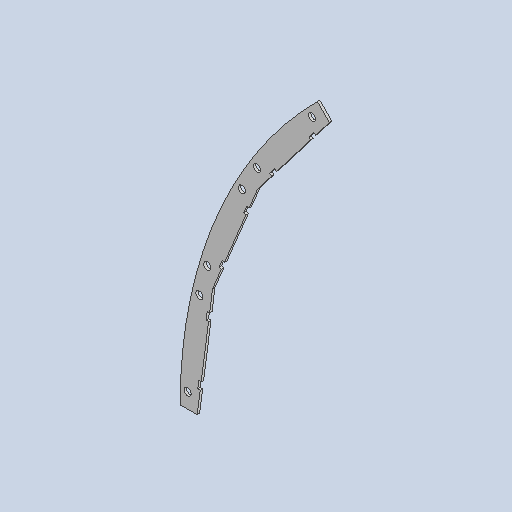
# Autodesk Inventor part: DMF-1209 Gear Rim 02
Saved by Autodesk Inventor 2026.2 (Build 302298000, 298)
## iProperties
Created: 2024-04-30
Part Number: DMF-1209 Gear Rim 02
Material: Stainless Steel
Document SubType Name: Sheet Metal
Designer: admin
Stock Number: DMF-1209
Mass: 249.053 g
Surface Area: 241.922 cm^2
Volume: 31.1317 cm^3
Density: 8 g/cm^3
Flat Pattern Width: 6.39586 cm
Flat Pattern Length: 44.6209 cm
Flat Pattern Area: 285.389 cm^2
Sheet Metal Rule: Default
Sheet Metal Width: 63,959 mm
Sheet Metal Length: 446,209 mm
Sheet Metal Area: 28538,909 mm^2
Appearance: Default
Rim1209_Chord_Length: 146,661 mm
Author: pokla
Autodesk Inventor part; units mm, degrees
ref_plane "YZ Plane" through (0, 0, 0) normal (1, 0, 0) x (0, 1, 0)
ref_plane "XZ Plane" through (0, 0, 0) normal (0, 1, 0) x (-1, 0, 0)
ref_plane "XY Plane" through (0, 0, 0) normal (0, 0, 1) x (1, 0, 0)
sketch "Sketch1" plane through (0, 0, 0) normal (0, 0, 1) x (1, 0, 0)
  line L0 (0, 0) -> (-583, 0) construction
  line L1 (0, 0) -> (-412.2433, 412.2433) construction
  arc A0 (-412.2433, 412.2433) -> (-583, 0) centre (0, 0) ccw
  line L2 (-561.8063, 0) -> (-542.6632, 145.4062)
  line L3 (-542.6632, 145.4062) -> (-486.5386, 280.9032)
  line L4 (-486.5386, 280.9032) -> (-397.2571, 397.2571)
  line L5 (-561.8063, 0) -> (-583, 0)
  line L6 (-397.2571, 397.2571) -> (-412.2433, 412.2433)
  line L7 (0, 0) -> (-561.8063, 0) construction
  line L8 (0, 0) -> (-542.6632, 145.4062) construction
  line L9 (0, 0) -> (-486.5386, 280.9032) construction
  line L10 (0, 0) -> (-397.2571, 397.2571) construction
  line L11 (0, 0) -> (-552.2348, 72.7031) construction
  dimension "Rim1209_Outer_Radius" = 583
  dimension "Rim1209_Angle" = 45
  dimension "Rim1209_Chord_Distance" = 557
  dimension "Rim1209_Chord_Length" = 146.6609
  constraints: 24 end point, 5 equal length, 2 point on circle, 2 point on line, 1 centre point, 1 coincident, 1 horizontal, 1 midpoint
  measures "Rim1209_Outer_Radius" radius of A0
  measures "Rim1209_Angle" angle of L0 L1
  measures "Rim1209_Chord_Distance" distance of L0.start L11.end
  measures "Rim1209_Chord_Length" distance of L2.start L2.end
extrude "Plate13" add sketch "Sketch1" along normal blind 3
sketch "Sketch2" plane through (0, 0, 3) normal (0, 0, 1) x (1, 0, 0)
  line L0 (-561.8063, 0) -> (-542.6632, 145.4062) construction
  line L1 (0, 0) -> (-552.2348, 72.7031) construction
  line L2 (-558.1085, 28.0881) -> (-556.8032, 38.0025)
  line L3 (-556.8032, 38.0025) -> (-559.7775, 38.3941)
  line L4 (-559.7775, 38.3941) -> (-561.0828, 28.4796)
  line L5 (-561.0828, 28.4796) -> (-558.1085, 28.0881)
  line L6 (-547.6664, 107.4037) -> (-546.3611, 117.3181)
  line L7 (-546.3611, 117.3181) -> (-549.3354, 117.7097)
  line L8 (-549.3354, 117.7097) -> (-550.6407, 107.7952)
  line L9 (-550.6407, 107.7952) -> (-547.6664, 107.4037)
  point P0 (-547.0137, 112.3609)
  point P1 (-557.4558, 33.0453)
  dimension "Rim1209_Slot_Length" = 10
  dimension "Rim1209_Slot_Depth" = 3
  dimension "Rim1209_Slot_Spacing" = 80
  constraints: 18 end point, 4 perpendicular, 3 midpoint, 2 collinear, 2 equal length, 2 parallel, 1 symmetric about line
  measures "Rim1209_Slot_Length" distance of L2.start L2.end
  measures "Rim1209_Slot_Depth" distance of L2.end L3.end
  measures "Rim1209_Slot_Spacing" distance of point (-547.014, 112.361) point (-557.456, 33.045)
extrude "Cut2" cut sketch "Sketch2" against normal blind 3
sketch "Sketch3" plane through (0, 0, 3) normal (0, 0, 1) x (1, 0, 0)
  line L0 (-561.8063, 0) -> (-542.6632, 145.4062) construction
  circle A0 centre (0, 0) radius 574 construction
  line L1 (0, 0) -> (-552.2348, 72.7031) construction
  circle A1 centre (-559.0054, 130.3418) radius 4.5
  line L2 (0, 0) -> (-559.0054, 130.3418) construction
  circle A2 centre (-573.6927, 18.7808) radius 4.5
  line L3 (0, 0) -> (-573.6927, 18.7808) construction
  dimension "d188" = 1148
  dimension "Rim1209_Hole_Diameter" = 9
  dimension "Rim1209_Hole_Angle" = 11.25
  constraints: 6 end point, 3 centre point, 2 point on circle, 1 coincident, 1 equal radius, 1 midpoint, 1 symmetric about line
  measures "d188" diameter of A0
  measures "Rim1209_Hole_Diameter" diameter of A1
  measures "Rim1209_Hole_Angle" angle of L2 L3
extrude "Cut3" cut sketch "Sketch3" against normal blind 3
pattern_circular "Circular Pattern7" count 3 over 30 about axis through (0, 0, -10) along (0, 0, -1) of "Cut2", "Cut3"
equation "\"BendRadius\" = Thickness"
equation "\"BendReliefWidth\" = Thickness"
equation "\"BendReliefDepth\" = 0.5 * Thickness"
equation "\"CornerReliefSize\" = 4 * Thickness"
equation "\"MinimumRemnant\" = 2 * Thickness"
equation "\"TransitionRadius\" = BendRadius"
equation "\"JacobiRadiusSize\" = BendRadius"
equation "\"GapSize\" = Thickness"
equation "\"Thickness\" = 3"
body "Solid6"
